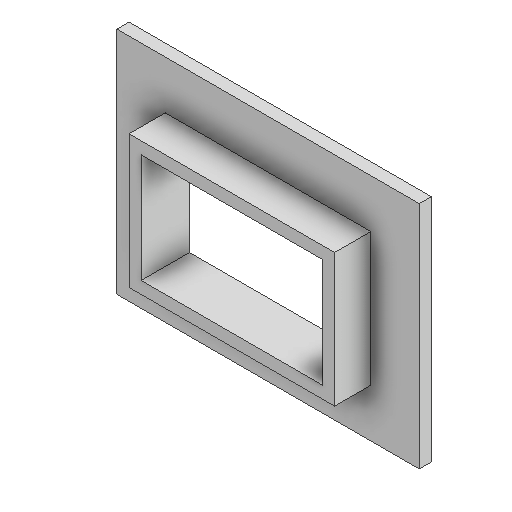
# Autodesk Inventor part: marco3
Saved by Autodesk Inventor 2025.2 (Build 292293000, 293)
## iProperties
Created: 2026-09-22
Part Number: marco3
Material: Genérico
Document SubType Name: Modeling
Designer: autor
Density: 1 g/cm^3
Appearance: Valor por defecto
Author: autor
Autodesk Inventor part; units mm, degrees
ref_plane "YZ Plane" through (0, 0, 0) normal (1, 0, 0) x (0, 1, 0)
ref_plane "XZ Plane" through (0, 0, 0) normal (0, 1, 0) x (-1, 0, 0)
ref_plane "XY Plane" through (0, 0, 0) normal (0, 0, 1) x (1, 0, 0)
sketch "Boceto1" plane through (0, 0, 0) normal (0, 0, 1) x (1, 0, 0)
  line L0 (-8.3049, 3.4946) -> (8.6951, 3.4946)
  line L1 (8.6951, 3.4946) -> (8.6951, -7.5054)
  line L2 (8.6951, -7.5054) -> (-8.3049, -7.5054)
  line L3 (-8.3049, -7.5054) -> (-8.3049, 3.4946)
  line L4 (12.6951, 7.4946) -> (-12.3049, 7.4946)
  line L5 (-12.3049, 7.4946) -> (-12.3049, -11.5054)
  line L6 (-12.3049, -11.5054) -> (12.6951, -11.5054)
  line L7 (12.6951, -11.5054) -> (12.6951, 7.4946)
  point P0 (0, 0)
  dimension "d0" = 17
  dimension "d1" = 11
  dimension "d2" = 4
  constraints: 16 end point, 4 parallel, 2 perpendicular, 1 horizontal, 3 other
  measures "d0" distance of L1.end L2.end
  measures "d1" distance of L0.end L1.end
  measures "d2" distance between parallel lines of L0 L4
extrude "Extrusión1" add sketch "Boceto1" along normal blind 1
sketch "Boceto2" plane through (0, 0, 1) normal (0, 0, 1) x (1, 0, 0)
  line L0 (-8.3049, 3.4946) -> (8.6951, 3.4946) projected
  line L1 (-8.3049, -7.5054) -> (-8.3049, 3.4946) projected
  line L2 (8.6951, -7.5054) -> (-8.3049, -7.5054) projected
  line L3 (8.6951, 3.4946) -> (8.6951, -7.5054) projected
  line L4 (7.6951, 2.4946) -> (-7.3049, 2.4946)
  line L5 (-7.3049, 2.4946) -> (-7.3049, -6.5054)
  line L6 (-7.3049, -6.5054) -> (7.6951, -6.5054)
  line L7 (7.6951, -6.5054) -> (7.6951, 2.4946)
  point P0 (0, 0)
  dimension "d5" = 1
  constraints: 8 end point, 3 other
  measures "d5" distance between parallel lines of L0 L4
extrude "Extrusión2" add sketch "Boceto2" along normal blind 3 and the other way blind 1
